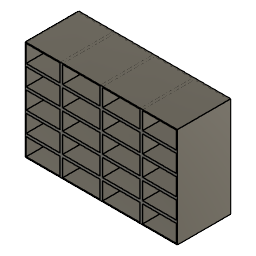
Z-Tray Holder (Autodesk Fusion 360 design; units mm, degrees)
Autodesk Fusion 360 part; units mm, degrees
note: some values were not read from the file. Set by a fixed rule: which face or edge a step refers to.
sketch "Sketch1" plane through (0, 0, 0) normal (0, 1, 0) x (1, 0, 0)
  line L0 (0, 0) -> (350, 0)
  line L1 (350, 0) -> (350, -230)
  line L2 (350, -230) -> (0, -230)
  line L3 (0, -230) -> (0, 0)
  dimension "d1" = 350
  dimension "d2" = 230
  constraint horizontal L0
  constraint vertical L1
  constraint horizontal L2
  constraint vertical L3
  constraint coincident L0.start L3.end
  measures "d1" distance of L0.start L0.end
  measures "d2" distance of L0.start L2.end
extrude "Extrude1" add sketch "Sketch1" along normal blind 123
sketch "Sketch2" plane through (0, 0, 0) normal (0, -1, 0) x (1, 0, 0)
  line L0 (350, 230) -> (0, 230)
  line L1 (0, 230) -> (0, 0)
  line L2 (0, 0) -> (350, 0)
  line L3 (350, 0) -> (350, 230)
  line L4 (0, 230) -> (2, 230)
  line L5 (2, 230) -> (2, 228)
  line L6 (2, 228) -> (0, 228)
  line L7 (0, 228) -> (0, 230)
  line L8 (2, 228) -> (72, 228)
  line L9 (72, 228) -> (72, 188)
  line L10 (72, 188) -> (2, 188)
  line L11 (2, 188) -> (2, 228)
  dimension "d5" = 2
  dimension "d6" = 2
  dimension "d7" = 70
  dimension "d8" = 40
  constraint horizontal L4
  constraint vertical L5
  constraint horizontal L6
  constraint vertical L7
  constraint coincident L0.end L1.start
  constraint horizontal L8
  constraint vertical L9
  constraint horizontal L10
  constraint vertical L11
  measures "d5" distance of L0.end L4.end
  measures "d6" distance of L0.end L6.end
  measures "d7" distance of L5.end L8.end
  measures "d8" distance of L5.end L10.end
extrude "Extrude2" cut sketch "Sketch2" against normal blind 120 contours L8 L9 L10 L11
pattern_linear "R-Pattern1" count 5 spacing 46.5 along (0, 0, -1) count 4 spacing 92 along (1, 0, 0) of 5 faces at (72, 40, 214.6667) (25.3333, 120, 201.3333) (48.6667, 40, 188) (25.3333, 40, 228) (2, 40, 201.3333)
extrude "Extrude3" cut 5 faces at (72, 40, 214.6667) (72, 40, 168.1667) (72, 40, 121.6667) (72, 40, 75.1667) (72, 40, 28.6667) along direction (1, 0, 0) blind 8
extrude "Extrude4" cut 5 faces at (94, 40, 201.3333) (94, 40, 154.8333) (94, 40, 108.3333) (94, 40, 61.8333) (94, 40, 15.3333) along direction (-1, 0, 0) blind 8
extrude "Extrude5" cut 5 faces at (164, 40, 214.6667) (164, 40, 168.1667) (164, 40, 121.6667) (164, 40, 75.1667) (164, 40, 28.6667) along direction (1, 0, 0) blind 8
extrude "Extrude6" cut 5 faces at (256, 40, 28.6667) (256, 40, 75.1667) (256, 40, 121.6667) (256, 40, 168.1667) (256, 40, 214.6667) along direction (1, 0, 0) blind 8
extrude "Extrude7" cut 5 faces at (278, 40, 15.3333) (278, 40, 61.8333) (278, 40, 108.3333) (278, 40, 154.8333) (278, 40, 201.3333) along direction (-1, 0, 0) blind 8
extrude "Extrude8" cut 5 faces at (186, 40, 201.3333) (186, 40, 154.8333) (186, 40, 108.3333) (186, 40, 61.8333) (186, 40, 15.3333) along direction (-1, 0, 0) blind 8
